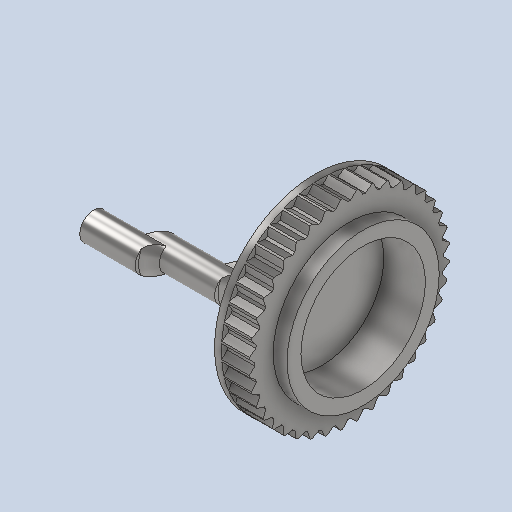
# Autodesk Inventor part: wheel
Saved by Autodesk Inventor 2026.1 (Build 301233020, 233B)
## iProperties
Created: 2025-11-26
Part Number: wheel
Material: Acciaio, Carbonio
Document SubType Name: Modeling
Designer: maxbu
Density: 7.85 g/cm^3
Appearance: Semilucidato
Mass: 21.1674 g
Surface Area: 26.8933 cm^2
Volume: 2.69649 cm^3
Author: maxbu
Autodesk Inventor part; units mm, degrees
ref_plane "YZ Plane" through (0, 0, 0) normal (1, 0, 0) x (0, 1, 0)
ref_plane "XZ Plane" through (0, 0, 0) normal (0, 1, 0) x (-1, 0, 0)
ref_plane "XY Plane" through (0, 0, 0) normal (0, 0, 1) x (1, 0, 0)
sketch "Schizzo1" plane through (0, 0, 0) normal (1, 0, 0) x (0, 1, 0)
  circle A0 centre (0, 0) radius 14.5
  line L0 (14.4655, 1) -> (13.6655, 0.2)
  line L1 (14.5, 0) -> (0, 0) construction
  line L2 (14.4655, -1) -> (13.6655, -0.2)
  line L3 (13.6655, 0.2) -> (13.6655, -0.2)
  line L4 (13.4655, 0) -> (13.6655, 0.2) construction
  line L5 (13.4655, 0) -> (13.6655, -0.2) construction
  line L6 (14.1309, 3.2506) -> (13.4659, 2.3353)
  line L7 (13.4659, 2.3353) -> (13.5285, 1.9402)
  line L8 (14.4438, 1.2752) -> (13.5285, 1.9402)
  line L9 (13.4485, 5.4211) -> (12.9348, 4.4131)
  line L10 (12.9348, 4.4131) -> (13.0584, 4.0327)
  line L11 (14.0665, 3.519) -> (13.0584, 4.0327)
  line L12 (12.4348, 7.4582) -> (12.0852, 6.3822)
  line L13 (12.0852, 6.3822) -> (12.2668, 6.0258)
  line L14 (13.3428, 5.6762) -> (12.2668, 6.0258)
  line L15 (11.115, 9.3116) -> (10.938, 8.1942)
  line L16 (10.938, 8.1942) -> (11.1732, 7.8706)
  line L17 (12.2906, 7.6936) -> (11.1732, 7.8706)
  line L18 (9.5215, 10.9357) -> (9.5215, 9.8044)
  line L19 (9.5215, 9.8044) -> (9.8044, 9.5215)
  line L20 (10.9357, 9.5215) -> (9.8044, 9.5215)
  line L21 (7.6936, 12.2906) -> (7.8706, 11.1732)
  line L22 (7.8706, 11.1732) -> (8.1942, 10.938)
  line L23 (9.3116, 11.115) -> (8.1942, 10.938)
  line L24 (5.6762, 13.3428) -> (6.0258, 12.2668)
  line L25 (6.0258, 12.2668) -> (6.3822, 12.0852)
  line L26 (7.4582, 12.4348) -> (6.3822, 12.0852)
  line L27 (3.519, 14.0665) -> (4.0327, 13.0584)
  line L28 (4.0327, 13.0584) -> (4.4131, 12.9348)
  line L29 (5.4211, 13.4485) -> (4.4131, 12.9348)
  line L30 (1.2752, 14.4438) -> (1.9402, 13.5285)
  line L31 (1.9402, 13.5285) -> (2.3353, 13.4659)
  line L32 (3.2506, 14.1309) -> (2.3353, 13.4659)
  line L33 (-1, 14.4655) -> (-0.2, 13.6655)
  line L34 (-0.2, 13.6655) -> (0.2, 13.6655)
  line L35 (1, 14.4655) -> (0.2, 13.6655)
  line L36 (-3.2506, 14.1309) -> (-2.3353, 13.4659)
  line L37 (-2.3353, 13.4659) -> (-1.9402, 13.5285)
  line L38 (-1.2752, 14.4438) -> (-1.9402, 13.5285)
  line L39 (-5.4211, 13.4485) -> (-4.4131, 12.9348)
  line L40 (-4.4131, 12.9348) -> (-4.0327, 13.0584)
  line L41 (-3.519, 14.0665) -> (-4.0327, 13.0584)
  line L42 (-7.4582, 12.4348) -> (-6.3822, 12.0852)
  line L43 (-6.3822, 12.0852) -> (-6.0258, 12.2668)
  line L44 (-5.6762, 13.3428) -> (-6.0258, 12.2668)
  line L45 (-9.3116, 11.115) -> (-8.1942, 10.938)
  line L46 (-8.1942, 10.938) -> (-7.8706, 11.1732)
  line L47 (-7.6936, 12.2906) -> (-7.8706, 11.1732)
  line L48 (-10.9357, 9.5215) -> (-9.8044, 9.5215)
  line L49 (-9.8044, 9.5215) -> (-9.5215, 9.8044)
  line L50 (-9.5215, 10.9357) -> (-9.5215, 9.8044)
  line L51 (-12.2906, 7.6936) -> (-11.1732, 7.8706)
  line L52 (-11.1732, 7.8706) -> (-10.938, 8.1942)
  line L53 (-11.115, 9.3116) -> (-10.938, 8.1942)
  line L54 (-13.3428, 5.6762) -> (-12.2668, 6.0258)
  line L55 (-12.2668, 6.0258) -> (-12.0852, 6.3822)
  line L56 (-12.4348, 7.4582) -> (-12.0852, 6.3822)
  line L57 (-14.0665, 3.519) -> (-13.0584, 4.0327)
  line L58 (-13.0584, 4.0327) -> (-12.9348, 4.4131)
  line L59 (-13.4485, 5.4211) -> (-12.9348, 4.4131)
  line L60 (-14.4438, 1.2752) -> (-13.5285, 1.9402)
  line L61 (-13.5285, 1.9402) -> (-13.4659, 2.3353)
  line L62 (-14.1309, 3.2506) -> (-13.4659, 2.3353)
  circle A1 centre (0, 0) radius 9
  line L63 (-14.4655, -1) -> (-13.6655, -0.2)
  line L64 (-13.6655, -0.2) -> (-13.6655, 0.2)
  line L65 (-14.4655, 1) -> (-13.6655, 0.2)
  line L66 (-14.1309, -3.2506) -> (-13.4659, -2.3353)
  line L67 (-13.4659, -2.3353) -> (-13.5285, -1.9402)
  line L68 (-14.4438, -1.2752) -> (-13.5285, -1.9402)
  line L69 (-13.4485, -5.4211) -> (-12.9348, -4.4131)
  line L70 (-12.9348, -4.4131) -> (-13.0584, -4.0327)
  line L71 (-14.0665, -3.519) -> (-13.0584, -4.0327)
  line L72 (-12.4348, -7.4582) -> (-12.0852, -6.3822)
  line L73 (-12.0852, -6.3822) -> (-12.2668, -6.0258)
  line L74 (-13.3428, -5.6762) -> (-12.2668, -6.0258)
  line L75 (-11.115, -9.3116) -> (-10.938, -8.1942)
  line L76 (-10.938, -8.1942) -> (-11.1732, -7.8706)
  line L77 (-12.2906, -7.6936) -> (-11.1732, -7.8706)
  line L78 (-9.5215, -10.9357) -> (-9.5215, -9.8044)
  line L79 (-9.5215, -9.8044) -> (-9.8044, -9.5215)
  line L80 (-10.9357, -9.5215) -> (-9.8044, -9.5215)
  line L81 (-7.6936, -12.2906) -> (-7.8706, -11.1732)
  line L82 (-7.8706, -11.1732) -> (-8.1942, -10.938)
  line L83 (-9.3116, -11.115) -> (-8.1942, -10.938)
  line L84 (-5.6762, -13.3428) -> (-6.0258, -12.2668)
  line L85 (-6.0258, -12.2668) -> (-6.3822, -12.0852)
  line L86 (-7.4582, -12.4348) -> (-6.3822, -12.0852)
  line L87 (-3.519, -14.0665) -> (-4.0327, -13.0584)
  line L88 (-4.0327, -13.0584) -> (-4.4131, -12.9348)
  line L89 (-5.4211, -13.4485) -> (-4.4131, -12.9348)
  line L90 (-1.2752, -14.4438) -> (-1.9402, -13.5285)
  line L91 (-1.9402, -13.5285) -> (-2.3353, -13.4659)
  line L92 (-3.2506, -14.1309) -> (-2.3353, -13.4659)
  line L93 (1, -14.4655) -> (0.2, -13.6655)
  line L94 (0.2, -13.6655) -> (-0.2, -13.6655)
  line L95 (-1, -14.4655) -> (-0.2, -13.6655)
  line L96 (3.2506, -14.1309) -> (2.3353, -13.4659)
  line L97 (2.3353, -13.4659) -> (1.9402, -13.5285)
  line L98 (1.2752, -14.4438) -> (1.9402, -13.5285)
  line L99 (5.4211, -13.4485) -> (4.4131, -12.9348)
  line L100 (4.4131, -12.9348) -> (4.0327, -13.0584)
  line L101 (3.519, -14.0665) -> (4.0327, -13.0584)
  line L102 (7.4582, -12.4348) -> (6.3822, -12.0852)
  line L103 (6.3822, -12.0852) -> (6.0258, -12.2668)
  line L104 (5.6762, -13.3428) -> (6.0258, -12.2668)
  line L105 (9.3116, -11.115) -> (8.1942, -10.938)
  line L106 (8.1942, -10.938) -> (7.8706, -11.1732)
  line L107 (7.6936, -12.2906) -> (7.8706, -11.1732)
  line L108 (10.9357, -9.5215) -> (9.8044, -9.5215)
  line L109 (9.8044, -9.5215) -> (9.5215, -9.8044)
  line L110 (9.5215, -10.9357) -> (9.5215, -9.8044)
  line L111 (12.2906, -7.6936) -> (11.1732, -7.8706)
  line L112 (11.1732, -7.8706) -> (10.938, -8.1942)
  line L113 (11.115, -9.3116) -> (10.938, -8.1942)
  line L114 (13.3428, -5.6762) -> (12.2668, -6.0258)
  line L115 (12.2668, -6.0258) -> (12.0852, -6.3822)
  line L116 (12.4348, -7.4582) -> (12.0852, -6.3822)
  line L117 (14.0665, -3.519) -> (13.0584, -4.0327)
  line L118 (13.0584, -4.0327) -> (12.9348, -4.4131)
  line L119 (13.4485, -5.4211) -> (12.9348, -4.4131)
  line L120 (14.4438, -1.2752) -> (13.5285, -1.9402)
  line L121 (13.5285, -1.9402) -> (13.4659, -2.3353)
  line L122 (14.1309, -3.2506) -> (13.4659, -2.3353)
  point P0 (14.4655, -1)
  point P1 (14.4438, 1.2752)
  point P2 (14.1309, 3.2506)
  point P3 (14.0665, 3.519)
  point P4 (13.4485, 5.4211)
  point P5 (13.3428, 5.6762)
  point P6 (12.4348, 7.4582)
  point P7 (12.2906, 7.6936)
  point P8 (11.115, 9.3116)
  point P9 (10.9357, 9.5215)
  point P10 (9.5215, 10.9357)
  point P11 (9.3116, 11.115)
  point P12 (7.6936, 12.2906)
  point P13 (7.4582, 12.4348)
  point P14 (5.6762, 13.3428)
  point P15 (3.519, 14.0665)
  point P16 (3.2506, 14.1309)
  point P17 (1.2752, 14.4438)
  point P18 (1, 14.4655)
  point P19 (-1, 14.4655)
  point P20 (-1.2752, 14.4438)
  point P21 (-3.2506, 14.1309)
  point P22 (-3.519, 14.0665)
  point P23 (-5.4211, 13.4485)
  point P24 (-5.6762, 13.3428)
  point P25 (-7.4582, 12.4348)
  point P26 (-7.6936, 12.2906)
  point P27 (-9.3116, 11.115)
  point P28 (-9.5215, 10.9357)
  point P29 (-11.115, 9.3116)
  point P30 (-12.2906, 7.6936)
  point P31 (-12.4348, 7.4582)
  point P32 (-13.3428, 5.6762)
  point P33 (-13.4485, 5.4211)
  point P34 (-14.0665, 3.519)
  point P35 (-14.1309, 3.2506)
  point P36 (-14.4438, 1.2752)
  point P37 (-14.4655, 1)
  point P38 (-14.4655, -1)
  point P39 (-14.4438, -1.2752)
  point P40 (-14.1309, -3.2506)
  point P41 (-14.0665, -3.519)
  point P42 (-13.4485, -5.4211)
  point P43 (-13.3428, -5.6762)
  point P44 (-12.4348, -7.4582)
  point P45 (-12.2906, -7.6936)
  point P46 (-11.115, -9.3116)
  point P47 (-9.5215, -10.9357)
  point P48 (-9.3116, -11.115)
  point P49 (-7.6936, -12.2906)
  point P50 (-7.4582, -12.4348)
  point P51 (-5.6762, -13.3428)
  point P52 (-5.4211, -13.4485)
  point P53 (-3.519, -14.0665)
  point P54 (-3.2506, -14.1309)
  point P55 (-1.2752, -14.4438)
  point P56 (-1, -14.4655)
  point P57 (1, -14.4655)
  point P58 (1.2752, -14.4438)
  point P59 (3.2506, -14.1309)
  dimension "d0" = 29
  dimension "d7" = 1
  dimension "d8" = 1
  dimension "d13" = 0.4
  dimension "d16" = 360
  dimension "d18" = 18
  constraints: 246 end point, 2 coincident, 2 collinear, 1 centre point, 1 horizontal, 1 perpendicular, 1 point on line, 1 symmetric about line, 284 other
  measures "d7" horizontal distance of L0.start L4.start
  measures "d8" horizontal distance of L0.start L4.start
  measures "d13" distance of L2.end L0.end
  measures "d18" diameter of A1
extrude "Estrusione1" add sketch "Schizzo1" along normal blind 4 contours L0 L3 L2 A0 L120 L121 L122 L117 L118 L119 L114 L115 L116 L111 L112 L113 L108 L109 L110 L105 L106 L107 L102 L103 L104 L99 L100 L101 L96 L97 L98 L93 L94 L95 L90 L91 L92 L87 L88 L89 L84 L85 L86 L81 L82 L83 L78 L79 L80 L75 L76 L77 L72 L73 L74 L69 L70 L71 L66 L67 L68 L63 L64 L65 L60 L61 L62 L57 L58 L59 L54 L55 L56 L51 L52 L53 L48 L49 L50 L45 L46 L47 L42 L43 L44 L39 L40 L41 L36 L37 L38 L33 L34 L35 L30 L31 L32 L27 L28 L29 L24 L25 L26 L21 L22 L23 L18 L19 L20 L15 L16 L17 L12 L13 L14 L9 L10 L11 L6 L7 L8
sketch "Schizzo2" plane through (0, 0, 0) normal (-1, 0, 0) x (0, 0, 1)
  circle A0 centre (0, 0) radius 14.5
  dimension "d19" = 29
  constraints: 1 centre point, 1 coincident
  measures "d19" diameter of A0
extrude "Estrusione2" add sketch "Schizzo2" along normal blind 1
sketch "Schizzo3" plane through (-1, 0, 0) normal (-1, 0, 0) x (0, 0, 1)
  circle A0 centre (0, 0) radius 14.5 projected
  circle A1 centre (4, 0) radius 2
  line L0 (4, 0) -> (0, 0) construction
  dimension "d23" = 4
  dimension "d24" = 4
  constraints: 2 end point, 1 centre point, 1 horizontal
  measures "d23" diameter of A1
  measures "d24" distance of point (0, 0) L0.start
extrude "Estrusione3" add sketch "Schizzo3" along normal blind 6.5 contours A1
sketch "Schizzo4" plane through (-7.5, 0, 4) normal (-1, 0, 0) x (0, 0, 1)
  circle A0 centre (0, 0) radius 2 projected
  line L0 (-4, 0) -> (0, 0) construction
  circle A1 centre (2, 0) radius 2
  dimension "d27" = 6
  constraints: 2 end point, 1 centre point, 1 equal radius, 1 horizontal, 1 point on line
  measures "d27" distance of L0.start A1.centre
extrude "Estrusione4" add sketch "Schizzo4" along normal blind 9.5 contours A0 A1 | A0 A1 picked at (0.6757, 0) picked at (3.3154, 0.1537)
sketch "Schizzo5" plane through (-17, 0, 6) normal (-1, 0, 0) x (0, 0, 1)
  arc A0 (-1, -1.7321) -> (-1, 1.7321) centre (0, 0) ccw projected
  line L0 (-6, 0) -> (0, 0) construction
  circle A1 centre (2, 0) radius 2
  circle A2 centre (0, 0) radius 2 projected
  dimension "d30" = 8
  constraints: 2 end point, 1 centre point, 1 equal radius, 1 horizontal, 1 point on line
  measures "d30" distance of L0.start A1.centre
extrude "Estrusione5" add sketch "Schizzo5" along normal blind 8 contours A1 A0 | A0 A1
chamfer "Smusso1" distance 1.5 angle 45 6 edges at (-17, -1, 7.7321) (-17, 1, 7.7321) (-17, 0, 6) (-7.5, -1, 5.7321) (-7.5, 1, 5.7321) (-7.5, 0, 4)
sketch "Schizzo6" plane through (4, 0, 0) normal (1, 0, 0) x (0, 0, -1)
  circle A0 centre (0, 0) radius 11
  circle A1 centre (0, 0) radius 9 projected
  dimension "d37" = 2
  constraints: 1 centre point, 1 coincident
  measures "d37" radial gap between concentric circles of A0 A1
extrude "Estrusione6" add sketch "Schizzo6" along normal blind 2
